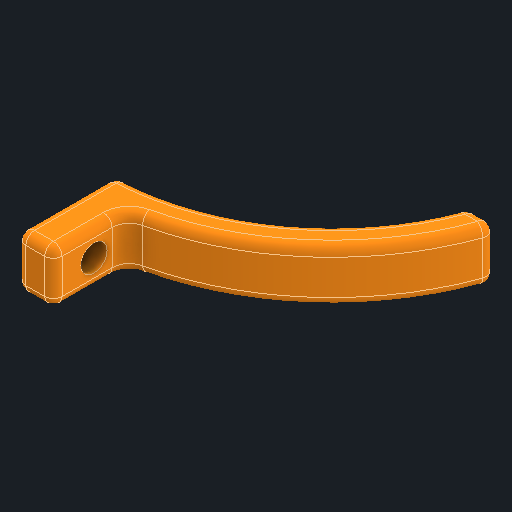
# Autodesk Inventor part: dec_band2_cap
Saved by Autodesk Inventor 2027.1 (Build 311270010, 270A)
## iProperties
Created: 2026-11-04
Part Number: dec_band2_cap
Material: Generic
Description: Dec band 2 cap (use 2): far-side quarter of band 2, hooks round the Dec housing up to the clutch boss, M4x16 into an insert in the bracket
Document SubType Name: Modeling
Designer: Claude (from photos)
Density: 1 g/cm^3
Appearance: Orange
Author: alexg
Autodesk Inventor part; units mm, degrees
ref_plane "Work Plane1" through (0, 61.5, 0) normal (0, 1, 0) x (-1, 0, 0)
sketch "Band 2 quarter sketch" plane through (0, 61.5, 0) normal (0, 1, 0) x (-1, 0, 0)
  circle A0 centre (-187, 0) radius 43
  circle A1 centre (-187, 0) radius 38
  constraints: 2 centre point
extrude "Band 2 quarter" add sketch "Band 2 quarter sketch" along normal blind 9
ref_plane "Work Plane2" through (0, 61.5, 0) normal (0, 1, 0) x (-1, 0, 0)
sketch "Keep the far half sketch" plane through (0, 61.5, 0) normal (0, 1, 0) x (-1, 0, 0)
  line L0 (-127, -60) -> (-187.75, -60)
  line L1 (-187.75, -60) -> (-187.75, 60)
  line L2 (-187.75, 60) -> (-127, 60)
  line L3 (-127, 60) -> (-127, -60)
  constraints: 8 end point, 2 parallel, 1 horizontal, 1 perpendicular
extrude "Keep the far half" cut sketch "Keep the far half sketch" along normal blind 9
ref_plane "Work Plane3" through (0, 61.5, 0) normal (0, 1, 0) x (-1, 0, 0)
sketch "Stop short of the Dec clutch boss sketch" plane through (0, 61.5, 0) normal (0, 1, 0) x (-1, 0, 0)
  line L0 (-127, -60) -> (-247, -60)
  line L1 (-247, -60) -> (-247, 12.5)
  line L2 (-247, 12.5) -> (-127, 12.5)
  line L3 (-127, 12.5) -> (-127, -60)
  constraints: 8 end point, 2 parallel, 1 horizontal, 1 perpendicular
extrude "Stop short of the Dec clutch boss" cut sketch "Stop short of the Dec clutch boss sketch" along normal blind 9
ref_plane "Work Plane4" through (0, 61.5, 0) normal (0, 1, 0) x (-1, 0, 0)
sketch "Clamp ear sketch" plane through (0, 61.5, 0) normal (0, 1, 0) x (-1, 0, 0)
  line L0 (-187.75, 41) -> (-194, 41)
  line L1 (-194, 41) -> (-194, 55)
  line L2 (-194, 55) -> (-187.75, 55)
  line L3 (-187.75, 55) -> (-187.75, 41)
  constraints: 8 end point, 2 parallel, 1 horizontal, 1 perpendicular
extrude "Clamp ear" add sketch "Clamp ear sketch" along normal blind 9
ref_plane "Work Plane5" through (187.75, 0, 0) normal (1, 0, 0) x (0, 1, 0)
sketch "M4 clearance hole sketch" plane through (187.75, 0, 0) normal (1, 0, 0) x (0, 1, 0)
  circle A0 centre (66, 48) radius 2.25
  constraints: 1 centre point
extrude "M4 clearance hole" cut sketch "M4 clearance hole sketch" along normal blind 10
fillet "Fillets (inside corners) R3 (1 edges)" radius 3 1 edges at (194, 66, 42.4264)
fillet "Rounds (outside edges) R1.5 (17 edges)" radius 1.5 17 edges at (194, 70.5, 49.9499) (194, 66, 55) (194, 61.5, 49.9499) (190.875, 61.5, 55) (190.875, 70.5, 55) (187.75, 66, 55) (216.2314, 61.5, 31.5361) (228.143, 66, 12.5) (216.2314, 70.5, 31.5361) (187.75, 61.5, 46.4963) (209.316, 61.5, 30.7571) (225.5141, 61.5, 12.5) (222.8852, 66, 12.5) (225.5141, 70.5, 12.5) (187.75, 70.5, 46.4963) (187.75, 66, 37.9926) (209.316, 70.5, 30.7571)
body "Solid1"
